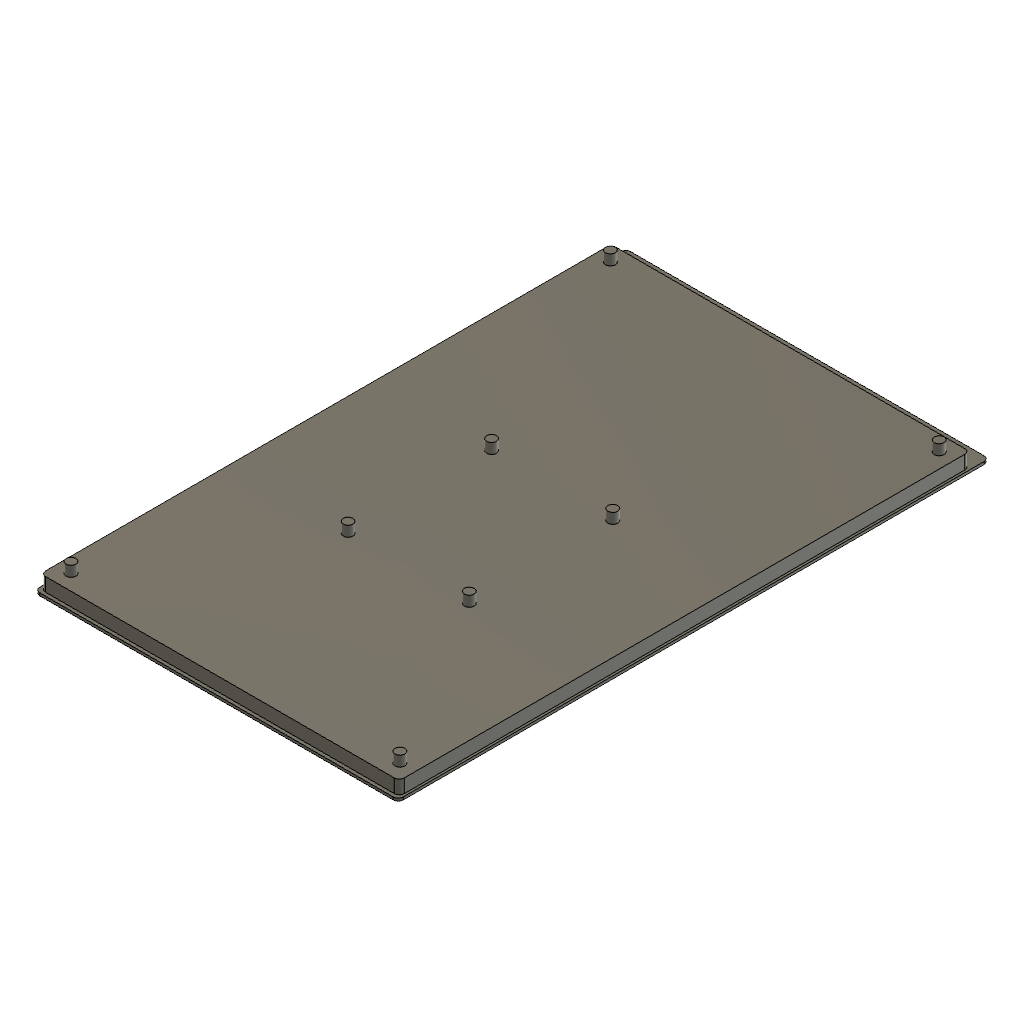
display_shell (Autodesk Fusion 360 design; units mm, degrees)
part number: 2026-10-27-17-07-03-425
part number: 2026-10-27-17-36-07-195
part number: 2026-10-27-17-36-17-819
Autodesk Fusion 360 part; units mm, degrees
sketch "Display" plane through (0, 0, 0) normal (0, 1, 0) x (1, 0, 0) in component "Display"
  line L0 (70.55, 115.35) -> (-70.55, 115.35)
  line L1 (-72.55, 113.35) -> (-72.55, -113.35)
  line L2 (-70.55, -115.35) -> (70.55, -115.35)
  line L3 (72.55, -113.35) -> (72.55, 113.35)
  line L4 (72.55, 115.35) -> (-72.55, -115.35) construction
  line L5 (-72.55, 115.35) -> (72.55, -115.35) construction
  line L6 (71.5, -116.72) -> (-71.5, -116.72)
  line L7 (-73.5, -114.72) -> (-73.5, 120.28)
  line L8 (-71.5, 122.28) -> (71.5, 122.28)
  line L9 (73.5, 120.28) -> (73.5, -114.72)
  arc A0 (-71.5, 122.28) -> (-73.5, 120.28) centre (-71.5, 120.28) ccw
  arc A1 (73.5, 120.28) -> (71.5, 122.28) centre (71.5, 120.28) ccw
  arc A2 (71.5, -116.72) -> (73.5, -114.72) centre (71.5, -114.72) ccw
  arc A3 (-73.5, -114.72) -> (-71.5, -116.72) centre (-71.5, -114.72) ccw
  arc A4 (-70.55, 115.35) -> (-72.55, 113.35) centre (-70.55, 113.35) ccw
  arc A5 (72.55, 113.35) -> (70.55, 115.35) centre (70.55, 113.35) ccw
  arc A6 (70.55, -115.35) -> (72.55, -113.35) centre (70.55, -113.35) ccw
  arc A7 (-72.55, -113.35) -> (-70.55, -115.35) centre (-70.55, -113.35) ccw
  circle A8 centre (-66.5, -109.05) radius 2
  circle A9 centre (66.5, -109.05) radius 2
  circle A10 centre (-66.5, 109.05) radius 2
  circle A11 centre (66.5, 109.05) radius 2
  circle A12 centre (-24.5, -39) radius 2
  circle A13 centre (24.5, -39) radius 2
  circle A14 centre (-24.5, 19) radius 2
  circle A15 centre (24.5, 19) radius 2
  line L10 (-67.98, -105.81) -> (67.98, -105.81)
  line L11 (67.98, -105.81) -> (67.98, 111.37)
  line L12 (67.98, 111.37) -> (-67.98, 111.37)
  line L13 (-67.98, 111.37) -> (-67.98, -105.81)
  point P0 (66.5, -109.05)
  point P1 (-66.5, -109.05)
  point P2 (66.5, 109.05)
  point P3 (-66.5, 109.05)
  point P4 (73.5, -116.72)
  point P5 (24.5, -39)
  point P6 (-24.5, -39)
  point P7 (24.5, 19)
  point P8 (-24.5, 19)
  point P9 (19.3, -68.25)
  point P10 (-24.7, -68.25)
  point P11 (-73.5, -116.72)
  point P12 (73.5, 122.28)
  dimension "d8" = 145.1
  dimension "d9" = 230.7
  dimension "d10" = 6.3
  dimension "d11" = 6.05
  dimension "d14" = -133
  dimension "d15" = 218.1
  dimension "d18" = 42
  dimension "d19" = 70.05
  dimension "d22" = -49
  dimension "d23" = 58
  dimension "d24" = 47.2
  dimension "d25" = 40.8
  dimension "d26" = 44
  dimension "d27" = 147
  dimension "d28" = 239
  dimension "d29" = 7.67
  dimension "d30" = 7
  dimension "d31" = 2
  dimension "d32" = 2
  dimension "d37" = 4
  dimension "d40" = 133
  dimension "d41" = 218.1
  dimension "d44" = 4
  dimension "d47" = 49
  dimension "d48" = 58
  dimension "d51" = 135.96
  dimension "d52" = 217.18
  dimension "d53" = 5.52
  dimension "d54" = 10.91
  constraint horizontal L0
  constraint perpendicular L0 L1
  constraint parallel L0 L2
  constraint parallel L1 L3
  constraint coincident L4 origin
  constraint coincident L5 origin
  constraint horizontal L6
  constraint vertical L7
  constraint horizontal L8
  constraint vertical L9
  constraint tangent L7 A0
  constraint tangent L8 A0
  constraint coincident P12 L8
  constraint coincident P12 L9
  constraint tangent L8 A1
  constraint tangent L9 A1
  constraint equal A0 A1
  constraint coincident P4 L9
  constraint coincident P4 L6
  constraint tangent L9 A2
  constraint tangent L6 A2
  constraint equal A0 A2
  constraint coincident P11 L6
  constraint coincident P11 L7
  constraint tangent L6 A3
  constraint tangent L7 A3
  constraint equal A0 A3
  constraint coincident L5.start L1
  constraint coincident L5.start L0
  constraint tangent L1 A4
  constraint tangent L0 A4
  constraint coincident L4.start L0
  constraint coincident L4.start L3
  constraint tangent L0 A5
  constraint tangent L3 A5
  constraint equal A4 A5
  constraint coincident L5.end L3
  constraint coincident L5.end L2
  constraint tangent L3 A6
  constraint tangent L2 A6
  constraint equal A4 A6
  constraint coincident L4.end L2
  constraint coincident L4.end L1
  constraint tangent L2 A7
  constraint tangent L1 A7
  constraint equal A4 A7
  constraint coincident P1 A8.centre
  constraint coincident P6 A12.centre
  constraint horizontal L10
  constraint vertical L11
  constraint horizontal L12
  constraint vertical L13
  measures "d8" distance of L4.end L5.end
  measures "d9" distance of L5.start L4.end
  measures "d10" distance of L2 P0
  measures "d11" distance of L3 P0
  measures "d18" horizontal distance of P2 P5
  measures "d19" vertical distance of P0 P5
  measures "d24" horizontal distance of P0 P9
  measures "d25" vertical distance of P0 P9
  measures "d26" distance of P9 P10
  measures "d27" distance of P4 P11
  measures "d28" distance of P4 P12
  measures "d29" distance of P1 L6
  measures "d30" distance of P2 L9
  measures "d31" radius of A0
  measures "d32" radius of A4
  measures "d37" diameter of A8
  measures "d44" diameter of A12
  measures "d51" distance of L10.start L10.end
  measures "d52" distance of L10.start L12.end
  measures "d53" distance of L7 L13
  measures "d54" distance of L8 L12
sketch "ESP32P4" plane through (0, 0, 0) normal (0, 1, 0) x (1, 0, 0) in component "ESP32P4"
  line L0 (27.5, 34) -> (-27.5, 34)
  line L1 (-27.5, 34) -> (-27.5, -34)
  line L2 (-27.5, -34) -> (27.5, -34)
  line L3 (27.5, -34) -> (27.5, 34)
  line L4 (27.5, 34) -> (-27.5, -34) construction
  line L5 (-27.5, 34) -> (27.5, -34) construction
  line L6 (24, 30) -> (-24, 30)
  line L7 (-24, 30) -> (-24, -3)
  line L8 (-24, -3) -> (24, -3)
  line L9 (24, -3) -> (24, 30)
  line L10 (24, 30) -> (-24, -3) construction
  line L11 (-24, 30) -> (24, -3) construction
  line L12 (2.43, -20) -> (2.43, -41.4036)
  line L13 (17.76, -20) -> (17.76, -42)
  point P0 (0, 13.5)
  dimension "d1" = 55
  dimension "d2" = 68
  dimension "d3" = 48
  dimension "d4" = 33
  dimension "d5" = 4
  dimension "d6" = 29.93
  dimension "d7" = 45.26
  constraint horizontal L0
  constraint perpendicular L0 L1
  constraint parallel L0 L2
  constraint parallel L1 L3
  constraint coincident L4 origin
  constraint coincident L5 origin
  constraint horizontal L6
  constraint perpendicular L6 L7
  constraint parallel L6 L8
  constraint parallel L7 L9
  constraint coincident L10 P0
  constraint coincident L11 P0
  constraint perpendicular L2 L12
  constraint vertical L13
  measures "d1" distance of L1.end L2.end
  measures "d2" distance of L0.end L1.end
  measures "d3" distance of L7.end L8.end
  measures "d4" distance of L6.end L7.end
  measures "d5" distance of L0 L6
  measures "d6" distance of L1 L12
  measures "d7" distance of L1 L13
extrude "Extrude1" add sketch "Display" along normal blind 1.1 contours L0 L1 L2 L3 A4 A5 A6 A7 | L6 L7 L8 L9 A0 A1 A2 A3 | A8 | A9 | A10 L13 | A10 A11 L10 L11 L12 L13 | A10 L13 | A11 L11 | A11 L11 | A12 | A13 | A14 | A15 in component "Display"
extrude "Extrude2" add sketch "Display" along normal blind 6.6 contours L0 L1 L2 L3 A4 A5 A6 A7 | A8 | A9 | A10 L13 | A10 A11 L10 L11 L12 L13 | A10 L13 | A11 L11 | A11 L11 | A12 | A13 | A14 | A15 in component "Display"
extrude "Extrude3" add sketch "Display" along normal blind 10.8 contours A8 | A9 | A10 L13 | A10 L13 | A11 L11 | A11 L11 in component "Display"
extrude "Extrude4" add sketch "Display" along normal blind 10.8 contours A12 | A13 | A14 | A15 in component "Display"
extrude "Extrude5" cut sketch "Display" along normal blind 0.01 contours A10 A11 L10 L11 L12 L13 in component "Display"
extrude "Extrude6" cut sketch "Display" along normal blind 0.001 contours A10 L13 | A10 A11 L10 L11 L12 L13 | A11 L11 picked at (-66.8465, 109.236) picked at (67.1578, 109.5824) in component "Display"
extrude "Extrude7" cut sketch "Display" along normal blind 0.01 contours A10 L13 | A10 A11 L10 L11 L12 L13 | A11 L11 | A12 | A13 | A14 | A15 picked at (-66.8465, 109.236) picked at (67.1578, 109.5824) in component "Display"
component "Display" placed x (1, 0, 0) y (0, 1, 0) z (0, 0, 1) at (0, 0, 0)
component "ESP32P4" placed x (1, 0, 0) y (0, 1, 0) z (0, 0, 1) at (0, 0, 0)
